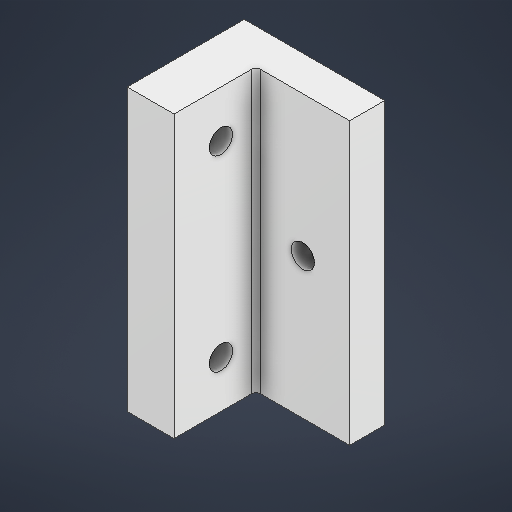
# Autodesk Inventor part: Acople caja 1
Saved by Autodesk Inventor 2027.1 (Build 311270010, 270A)
## iProperties
Created: 2026-10-01
Part Number: Acople caja 1
Material: Plástico ABS
Document SubType Name: Modeling
Designer: irene
Density: 1.06 g/cm^3
Appearance: Suave - Blanco
Author: irene
Autodesk Inventor part; units mm, degrees
ref_plane "YZ Plane" through (0, 0, 0) normal (1, 0, 0) x (0, 1, 0)
ref_plane "XZ Plane" through (0, 0, 0) normal (0, 1, 0) x (-1, 0, 0)
ref_plane "XY Plane" through (0, 0, 0) normal (0, 0, 1) x (1, 0, 0)
sketch "Boceto1" plane through (0, 0, 0) normal (1, 0, 0) x (0, 1, 0)
  line L0 (0, 0) -> (0, 25)
  line L1 (0, 25) -> (60, 25)
  line L2 (60, 25) -> (60, 0)
  line L3 (60, 0) -> (0, 0)
  circle A0 centre (50, 15) radius 2.5
  circle A1 centre (10, 15) radius 2.5
  line L4 (0, 0) -> (60, 0)
  point P0 (60, 12.5)
  dimension "d0" = 60
  dimension "d1" = 25
  dimension "d3" = 5
  dimension "d4" = 5
  dimension "d22" = 10
  dimension "d23" = 10
  dimension "d24" = 40
  dimension "d25" = 10
  constraints: 10 end point, 2 centre point, 2 parallel, 1 midpoint, 1 perpendicular, 1 vertical
  measures "d0" distance of L2.end L0.start
  measures "d1" distance of L1.end L2.end
  measures "d3" diameter of A0
  measures "d4" diameter of A1
  measures "d22" distance from line of A0.centre L1
  measures "d23" distance from line of L1 A1.centre
  measures "d24" distance of A1.centre A0.centre
  measures "d25" distance from line of L2 A0.centre
extrude "Extrusión1" add sketch "Boceto1" along normal blind 10
sketch "Boceto4" plane through (10, 0, 0) normal (1, 0, 0) x (0, 0, -1)
  line L0 (0, 60) -> (-25, 60) projected
  line L1 (0, 60) -> (-7.5, 60)
  line L2 (-7.5, 60) -> (-7.5, 0)
  line L3 (-7.5, 0) -> (0, 0)
  line L4 (0, 0) -> (0, 60)
  point P0 (0, 0)
  dimension "d26" = 7.5
  constraints: 8 end point, 2 parallel, 1 perpendicular, 1 point on line
  measures "d26" distance between parallel lines of L4 L2
extrude "Extrusión4" add sketch "Boceto4" along normal blind 20
fillet "Empalme2" radius 1 1 edges at (10, 30, 7.5)
sketch "Boceto5" plane through (30, 0, 7.5) normal (0, 0, 1) x (1, 0, 0)
  circle A0 centre (-10, 30) radius 2.5
  line L0 (-19, 60) -> (0, 60) projected
  line L1 (0, 60) -> (0, 0) projected
  point P0 (-30, 0)
  dimension "d30" = 5
  dimension "d31" = 30
  dimension "d32" = 10
  constraints: 1 centre point
  measures "d30" diameter of A0
  measures "d31" distance from line of L0 A0.centre
  measures "d32" distance from line of L1 A0.centre
extrude "Extrusión5" cut sketch "Boceto5" against normal through all
